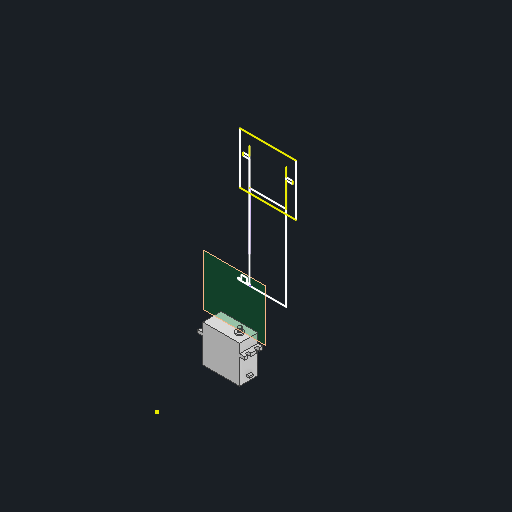
# Autodesk Inventor part: SERVO DS35MG IP67
Saved by Autodesk Inventor 2026.2 (Build 302298000, 298)
## iProperties
Created: 2026-01-28
Part Number: SERVO DS35MG IP67
Material: Generic
Document SubType Name: Modeling
Designer: thita
Density: 1 g/cm^3
Appearance: Default
Author: thita
Autodesk Inventor part; units mm, degrees
ref_plane "YZ Plane" through (0, 0, 0) normal (1, 0, 0) x (0, 1, 0)
ref_plane "XZ Plane" through (0, 0, 0) normal (0, 1, 0) x (-1, 0, 0)
ref_plane "XY Plane" through (0, 0, 0) normal (0, 0, 1) x (1, 0, 0)
sketch "Sketch1" plane through (0, 0, 0) normal (0, 1, 0) x (-1, 0, 0)
  line L0 (20, -10) -> (-20, -10)
  line L1 (-20, -10) -> (-20, 10)
  line L2 (-20, 10) -> (20, 10)
  line L3 (20, 10) -> (20, -10)
  line L4 (20, -10) -> (-20, 10) construction
  line L5 (-20, -10) -> (20, 10) construction
  point P0 (0, 0)
  dimension "d0" = 40
  dimension "d1" = 20
  constraints: 12 end point, 2 midpoint, 2 parallel, 1 horizontal, 1 perpendicular
  measures "d0" distance of L0.start L0.end
  measures "d1" distance of L0.end L1.end
extrude "Extrusion1" add sketch "Sketch1" along normal blind 40.5
sketch "Sketch2" plane through (0, 40.5, 0) normal (0, 1, 0) x (1, 0, 0)
  line L0 (20, -10) -> (20, 10) projected
  line L1 (20, 0) -> (10.2, 0)
  circle A0 centre (10.2, 0) radius 4
  point P0 (0, 0)
  dimension "d4" = 9.8
  dimension "d5" = 8
  constraints: 2 end point, 1 centre point, 1 coincident, 1 horizontal, 1 midpoint
  measures "d4" distance of L1.start L1.end
  measures "d5" diameter of A0
extrude "Extrusion2" add sketch "Sketch2" along normal blind 1.2
sketch "Sketch3" plane through (10.2, 41.7, 0) normal (0, 1, 0) x (1, 0, 0)
  circle A0 centre (0, 0) radius 2
  point P0 (-10.2, 0)
  dimension "d8" = 4
  constraints: 1 centre point
  measures "d8" diameter of A0
extrude "Extrusion3" add sketch "Sketch3" along normal blind 4.3
sketch "Sketch4" plane through (0, 0, 0) normal (0, -1, 0) x (1, 0, 0)
  arc A0 (25.5, -3.35) -> (25.5, -6.55) centre (24.3, -4.95) ccw
  arc A1 (-25.5, -6.55) -> (-25.5, -3.35) centre (-24.3, -4.95) ccw
  arc A2 (25.5, 6.55) -> (25.5, 3.35) centre (24.3, 4.95) ccw
  arc A3 (-25.5, 3.35) -> (-25.5, 6.55) centre (-24.3, 4.95) ccw
  line L0 (25.5, -6.55) -> (25.5, -10)
  line L1 (25.5, 10) -> (25.5, 6.55)
  line L2 (25.5, 3.35) -> (25.5, -3.35)
  line L3 (-25.5, 6.55) -> (-25.5, 10)
  line L4 (-25.5, -10) -> (-25.5, -6.55)
  line L5 (-25.5, -3.35) -> (-25.5, 3.35)
  line L6 (20, -10) -> (-20, -10) projected
  line L7 (25.5, -10) -> (20, -10)
  line L8 (20, -10) -> (20, 10)
  line L9 (20, 10) -> (25.5, 10)
  line L10 (-20, -10) -> (-25.5, -10)
  line L11 (-20, -10) -> (-20, 10) projected
  line L12 (-20, -10) -> (-20, 10)
  line L13 (-20, 10) -> (-25.5, 10)
  dimension "d14" = 4
  dimension "d15" = 4
  dimension "d16" = 4
  dimension "d17" = 4
  dimension "d19" = 20
  dimension "d20" = 20
  constraints: 24 end point, 10 parallel, 8 point on circle, 4 centre point, 3 perpendicular, 3 vertical, 1 collinear, 1 horizontal
  measures "d14" diameter of A0
  measures "d15" diameter of A1
  measures "d16" diameter of A2
  measures "d17" diameter of A3
  measures "d19" distance of L1.start L0.end
  measures "d20" distance of L4.start L3.end
extrude "Extrusion4" add sketch "Sketch4" against normal blind 30.5
sketch "Sketch5" plane through (0, 0, 0) normal (0, -1, 0) x (1, 0, 0)
  line L0 (20, -10) -> (-20, -10) projected
  line L1 (-20, 10) -> (20, 10) projected
  line L2 (20, -10) -> (20, 10)
  line L3 (-25.5, 10) -> (25.5, 10) projected
  line L4 (20, 10) -> (25.5, 10)
  line L5 (20, -10) -> (25.5, -10)
  arc A0 (25.5, -3.35) -> (25.5, -6.55) centre (24.3, -4.95) ccw projected
  arc A1 (25.5, -3.35) -> (25.5, -6.55) centre (24.3, -4.95) ccw
  arc A2 (25.5, 6.55) -> (25.5, 3.35) centre (24.3, 4.95) ccw projected
  arc A3 (25.5, 6.55) -> (25.5, 3.35) centre (24.3, 4.95) ccw
  line L6 (25.5, -10) -> (25.5, -6.55)
  line L7 (25.5, -3.35) -> (25.5, 3.35)
  line L8 (25.5, 6.55) -> (25.5, 10)
  line L9 (0, -10) -> (0, 10)
  line L10 (-20, -10) -> (-20, 10)
  line L11 (-20, 10) -> (-25.5, 10)
  line L12 (-20, -10) -> (-25.5, -10)
  arc A4 (-25.5, -6.55) -> (-25.5, -3.35) centre (-24.3, -4.95) ccw
  arc A5 (-25.5, -6.55) -> (-25.5, -3.35) centre (-24.3, -4.95) ccw
  arc A6 (-25.5, 3.35) -> (-25.5, 6.55) centre (-24.3, 4.95) ccw
  arc A7 (-25.5, 3.35) -> (-25.5, 6.55) centre (-24.3, 4.95) ccw
  line L13 (-25.5, -10) -> (-25.5, -6.55)
  line L14 (-25.5, -3.35) -> (-25.5, 3.35)
  line L15 (-25.5, 6.55) -> (-25.5, 10)
  point P0 (0, 0)
  point P1 (25.5, 3.35)
  constraints: 26 end point, 13 symmetric about line, 12 point on circle, 6 centre point, 4 coincident, 4 perpendicular, 2 midpoint, 1 collinear, 1 vertical, 4 other
extrude "Extrusion5" cut sketch "Sketch5" against normal blind 27.3 contours L2 L3 L8 A2 L7 A0 L6 L5 | L12 L13 A4 L14 A6 L15 L3 L10
sketch "Sketch6" plane through (10.2, 46, 0) normal (0, 1, 0) x (1, 0, 0)
  circle A0 centre (0, 0) radius 2 projected
  line L0 (0.0494, -1.9994) -> (0, -1.9)
  line L1 (-0.0494, -1.9994) -> (0, -1.9)
  line L2 (0.1748, -1.9923) -> (0.1193, -1.8963)
  line L3 (0.0763, -1.9985) -> (0.1193, -1.8963)
  line L4 (0.2996, -1.9774) -> (0.2381, -1.885)
  line L5 (0.2016, -1.9898) -> (0.2381, -1.885)
  line L6 (0.4232, -1.9547) -> (0.356, -1.8663)
  line L7 (0.3261, -1.9732) -> (0.356, -1.8663)
  line L8 (0.5451, -1.9243) -> (0.4725, -1.8403)
  line L9 (0.4494, -1.9489) -> (0.4725, -1.8403)
  line L10 (0.6648, -1.8863) -> (0.5871, -1.807)
  line L11 (0.5709, -1.9168) -> (0.5871, -1.807)
  line L12 (0.7819, -1.8408) -> (0.6994, -1.7666)
  line L13 (0.6901, -1.8772) -> (0.6994, -1.7666)
  line L14 (0.896, -1.7881) -> (0.809, -1.7192)
  line L15 (0.8066, -1.8301) -> (0.809, -1.7192)
  line L16 (1.0065, -1.7283) -> (0.9153, -1.665)
  line L17 (0.9199, -1.7759) -> (0.9153, -1.665)
  line L18 (1.113, -1.6617) -> (1.0181, -1.6042)
  line L19 (1.0296, -1.7146) -> (1.0181, -1.6042)
  line L20 (1.2152, -1.5885) -> (1.1168, -1.5371)
  line L21 (1.1353, -1.6466) -> (1.1168, -1.5371)
  line L22 (1.3125, -1.5091) -> (1.2111, -1.464)
  line L23 (1.2364, -1.572) -> (1.2111, -1.464)
  line L24 (1.4047, -1.4237) -> (1.3006, -1.385)
  line L25 (1.3327, -1.4913) -> (1.3006, -1.385)
  line L26 (1.4913, -1.3327) -> (1.385, -1.3006)
  line L27 (1.4237, -1.4047) -> (1.385, -1.3006)
  line L28 (1.572, -1.2364) -> (1.464, -1.2111)
  line L29 (1.5091, -1.3125) -> (1.464, -1.2111)
  line L30 (1.6466, -1.1353) -> (1.5371, -1.1168)
  line L31 (1.5885, -1.2152) -> (1.5371, -1.1168)
  line L32 (1.7146, -1.0296) -> (1.6042, -1.0181)
  line L33 (1.6617, -1.113) -> (1.6042, -1.0181)
  line L34 (1.7759, -0.9199) -> (1.665, -0.9153)
  line L35 (1.7283, -1.0065) -> (1.665, -0.9153)
  line L36 (1.8301, -0.8066) -> (1.7192, -0.809)
  line L37 (1.7881, -0.896) -> (1.7192, -0.809)
  line L38 (1.8772, -0.6901) -> (1.7666, -0.6994)
  line L39 (1.8408, -0.7819) -> (1.7666, -0.6994)
  line L40 (1.9168, -0.5709) -> (1.807, -0.5871)
  line L41 (1.8863, -0.6648) -> (1.807, -0.5871)
  line L42 (1.9489, -0.4494) -> (1.8403, -0.4725)
  line L43 (1.9243, -0.5451) -> (1.8403, -0.4725)
  line L44 (1.9732, -0.3261) -> (1.8663, -0.356)
  line L45 (1.9547, -0.4232) -> (1.8663, -0.356)
  line L46 (1.9898, -0.2016) -> (1.885, -0.2381)
  line L47 (1.9774, -0.2996) -> (1.885, -0.2381)
  line L48 (1.9985, -0.0763) -> (1.8963, -0.1193)
  line L49 (1.9923, -0.1748) -> (1.8963, -0.1193)
  line L50 (1.9994, 0.0494) -> (1.9, 0)
  line L51 (1.9994, -0.0494) -> (1.9, 0)
  line L52 (1.9923, 0.1748) -> (1.8963, 0.1193)
  line L53 (1.9985, 0.0763) -> (1.8963, 0.1193)
  line L54 (1.9774, 0.2996) -> (1.885, 0.2381)
  line L55 (1.9898, 0.2016) -> (1.885, 0.2381)
  line L56 (1.9547, 0.4232) -> (1.8663, 0.356)
  line L57 (1.9732, 0.3261) -> (1.8663, 0.356)
  line L58 (1.9243, 0.5451) -> (1.8403, 0.4725)
  line L59 (1.9489, 0.4494) -> (1.8403, 0.4725)
  line L60 (1.8863, 0.6648) -> (1.807, 0.5871)
  line L61 (1.9168, 0.5709) -> (1.807, 0.5871)
  line L62 (1.8408, 0.7819) -> (1.7666, 0.6994)
  line L63 (1.8772, 0.6901) -> (1.7666, 0.6994)
  line L64 (1.7881, 0.896) -> (1.7192, 0.809)
  line L65 (1.8301, 0.8066) -> (1.7192, 0.809)
  line L66 (1.7283, 1.0065) -> (1.665, 0.9153)
  line L67 (1.7759, 0.9199) -> (1.665, 0.9153)
  line L68 (1.6617, 1.113) -> (1.6042, 1.0181)
  line L69 (1.7146, 1.0296) -> (1.6042, 1.0181)
  line L70 (1.5885, 1.2152) -> (1.5371, 1.1168)
  line L71 (1.6466, 1.1353) -> (1.5371, 1.1168)
  line L72 (1.5091, 1.3125) -> (1.464, 1.2111)
  line L73 (1.572, 1.2364) -> (1.464, 1.2111)
  line L74 (1.4237, 1.4047) -> (1.385, 1.3006)
  line L75 (1.4913, 1.3327) -> (1.385, 1.3006)
  line L76 (1.3327, 1.4913) -> (1.3006, 1.385)
  line L77 (1.4047, 1.4237) -> (1.3006, 1.385)
  line L78 (1.2364, 1.572) -> (1.2111, 1.464)
  line L79 (1.3125, 1.5091) -> (1.2111, 1.464)
  line L80 (1.1353, 1.6466) -> (1.1168, 1.5371)
  line L81 (1.2152, 1.5885) -> (1.1168, 1.5371)
  line L82 (1.0296, 1.7146) -> (1.0181, 1.6042)
  line L83 (1.113, 1.6617) -> (1.0181, 1.6042)
  line L84 (0.9199, 1.7759) -> (0.9153, 1.665)
  line L85 (1.0065, 1.7283) -> (0.9153, 1.665)
  line L86 (0.8066, 1.8301) -> (0.809, 1.7192)
  line L87 (0.896, 1.7881) -> (0.809, 1.7192)
  line L88 (0.6901, 1.8772) -> (0.6994, 1.7666)
  line L89 (0.7819, 1.8408) -> (0.6994, 1.7666)
  line L90 (0.5709, 1.9168) -> (0.5871, 1.807)
  line L91 (0.6648, 1.8863) -> (0.5871, 1.807)
  line L92 (0.4494, 1.9489) -> (0.4725, 1.8403)
  line L93 (0.5451, 1.9243) -> (0.4725, 1.8403)
  line L94 (0.3261, 1.9732) -> (0.356, 1.8663)
  line L95 (0.4232, 1.9547) -> (0.356, 1.8663)
  line L96 (0.2016, 1.9898) -> (0.2381, 1.885)
  line L97 (0.2996, 1.9774) -> (0.2381, 1.885)
  line L98 (0.0763, 1.9985) -> (0.1193, 1.8963)
  line L99 (0.1748, 1.9923) -> (0.1193, 1.8963)
  line L100 (-0.0494, 1.9994) -> (0, 1.9)
  line L101 (0.0494, 1.9994) -> (0, 1.9)
  line L102 (-0.1748, 1.9923) -> (-0.1193, 1.8963)
  line L103 (-0.0763, 1.9985) -> (-0.1193, 1.8963)
  line L104 (-0.2996, 1.9774) -> (-0.2381, 1.885)
  line L105 (-0.2016, 1.9898) -> (-0.2381, 1.885)
  line L106 (-0.4232, 1.9547) -> (-0.356, 1.8663)
  line L107 (-0.3261, 1.9732) -> (-0.356, 1.8663)
  line L108 (-0.5451, 1.9243) -> (-0.4725, 1.8403)
  line L109 (-0.4494, 1.9489) -> (-0.4725, 1.8403)
  line L110 (-0.6648, 1.8863) -> (-0.5871, 1.807)
  line L111 (-0.5709, 1.9168) -> (-0.5871, 1.807)
  line L112 (-0.7819, 1.8408) -> (-0.6994, 1.7666)
  line L113 (-0.6901, 1.8772) -> (-0.6994, 1.7666)
  line L114 (-0.896, 1.7881) -> (-0.809, 1.7192)
  line L115 (-0.8066, 1.8301) -> (-0.809, 1.7192)
  line L116 (-1.0065, 1.7283) -> (-0.9153, 1.665)
  line L117 (-0.9199, 1.7759) -> (-0.9153, 1.665)
  line L118 (-1.113, 1.6617) -> (-1.0181, 1.6042)
  line L119 (-1.0296, 1.7146) -> (-1.0181, 1.6042)
  line L120 (-1.2152, 1.5885) -> (-1.1168, 1.5371)
  line L121 (-1.1353, 1.6466) -> (-1.1168, 1.5371)
  line L122 (-1.3125, 1.5091) -> (-1.2111, 1.464)
  line L123 (-1.2364, 1.572) -> (-1.2111, 1.464)
  line L124 (-1.4047, 1.4237) -> (-1.3006, 1.385)
  line L125 (-1.3327, 1.4913) -> (-1.3006, 1.385)
  line L126 (-1.4913, 1.3327) -> (-1.385, 1.3006)
  line L127 (-1.4237, 1.4047) -> (-1.385, 1.3006)
  line L128 (-1.572, 1.2364) -> (-1.464, 1.2111)
  line L129 (-1.5091, 1.3125) -> (-1.464, 1.2111)
  line L130 (-1.6466, 1.1353) -> (-1.5371, 1.1168)
  line L131 (-1.5885, 1.2152) -> (-1.5371, 1.1168)
  line L132 (-1.7146, 1.0296) -> (-1.6042, 1.0181)
  line L133 (-1.6617, 1.113) -> (-1.6042, 1.0181)
  line L134 (-1.7759, 0.9199) -> (-1.665, 0.9153)
  line L135 (-1.7283, 1.0065) -> (-1.665, 0.9153)
  line L136 (-1.8301, 0.8066) -> (-1.7192, 0.809)
  line L137 (-1.7881, 0.896) -> (-1.7192, 0.809)
  line L138 (-1.8772, 0.6901) -> (-1.7666, 0.6994)
  line L139 (-1.8408, 0.7819) -> (-1.7666, 0.6994)
  line L140 (-1.9168, 0.5709) -> (-1.807, 0.5871)
  line L141 (-1.8863, 0.6648) -> (-1.807, 0.5871)
  line L142 (-1.9489, 0.4494) -> (-1.8403, 0.4725)
  line L143 (-1.9243, 0.5451) -> (-1.8403, 0.4725)
  line L144 (-1.9732, 0.3261) -> (-1.8663, 0.356)
  line L145 (-1.9547, 0.4232) -> (-1.8663, 0.356)
  line L146 (-1.9898, 0.2016) -> (-1.885, 0.2381)
  line L147 (-1.9774, 0.2996) -> (-1.885, 0.2381)
  line L148 (-1.9985, 0.0763) -> (-1.8963, 0.1193)
  line L149 (-1.9923, 0.1748) -> (-1.8963, 0.1193)
  line L150 (-1.9994, -0.0494) -> (-1.9, 0)
  line L151 (-1.9994, 0.0494) -> (-1.9, 0)
  line L152 (-1.9923, -0.1748) -> (-1.8963, -0.1193)
  line L153 (-1.9985, -0.0763) -> (-1.8963, -0.1193)
  line L154 (-1.9774, -0.2996) -> (-1.885, -0.2381)
  line L155 (-1.9898, -0.2016) -> (-1.885, -0.2381)
  line L156 (-1.9547, -0.4232) -> (-1.8663, -0.356)
  line L157 (-1.9732, -0.3261) -> (-1.8663, -0.356)
  line L158 (-1.9243, -0.5451) -> (-1.8403, -0.4725)
  line L159 (-1.9489, -0.4494) -> (-1.8403, -0.4725)
  line L160 (-1.8863, -0.6648) -> (-1.807, -0.5871)
  line L161 (-1.9168, -0.5709) -> (-1.807, -0.5871)
  line L162 (-1.8408, -0.7819) -> (-1.7666, -0.6994)
  line L163 (-1.8772, -0.6901) -> (-1.7666, -0.6994)
  line L164 (-1.7881, -0.896) -> (-1.7192, -0.809)
  line L165 (-1.8301, -0.8066) -> (-1.7192, -0.809)
  line L166 (-1.7283, -1.0065) -> (-1.665, -0.9153)
  line L167 (-1.7759, -0.9199) -> (-1.665, -0.9153)
  line L168 (-1.6617, -1.113) -> (-1.6042, -1.0181)
  line L169 (-1.7146, -1.0296) -> (-1.6042, -1.0181)
  line L170 (-1.5885, -1.2152) -> (-1.5371, -1.1168)
  line L171 (-1.6466, -1.1353) -> (-1.5371, -1.1168)
  line L172 (-1.5091, -1.3125) -> (-1.464, -1.2111)
  line L173 (-1.572, -1.2364) -> (-1.464, -1.2111)
  line L174 (-1.4237, -1.4047) -> (-1.385, -1.3006)
  line L175 (-1.4913, -1.3327) -> (-1.385, -1.3006)
  line L176 (-1.3327, -1.4913) -> (-1.3006, -1.385)
  line L177 (-1.4047, -1.4237) -> (-1.3006, -1.385)
  line L178 (-1.2364, -1.572) -> (-1.2111, -1.464)
  line L179 (-1.3125, -1.5091) -> (-1.2111, -1.464)
  line L180 (-1.1353, -1.6466) -> (-1.1168, -1.5371)
  line L181 (-1.2152, -1.5885) -> (-1.1168, -1.5371)
  line L182 (-1.0296, -1.7146) -> (-1.0181, -1.6042)
  line L183 (-1.113, -1.6617) -> (-1.0181, -1.6042)
  line L184 (-0.9199, -1.7759) -> (-0.9153, -1.665)
  line L185 (-1.0065, -1.7283) -> (-0.9153, -1.665)
  line L186 (-0.8066, -1.8301) -> (-0.809, -1.7192)
  line L187 (-0.896, -1.7881) -> (-0.809, -1.7192)
  line L188 (-0.6901, -1.8772) -> (-0.6994, -1.7666)
  line L189 (-0.7819, -1.8408) -> (-0.6994, -1.7666)
  line L190 (-0.5709, -1.9168) -> (-0.5871, -1.807)
  line L191 (-0.6648, -1.8863) -> (-0.5871, -1.807)
  line L192 (-0.4494, -1.9489) -> (-0.4725, -1.8403)
  line L193 (-0.5451, -1.9243) -> (-0.4725, -1.8403)
  line L194 (-0.3261, -1.9732) -> (-0.356, -1.8663)
  line L195 (-0.4232, -1.9547) -> (-0.356, -1.8663)
  line L196 (-0.2016, -1.9898) -> (-0.2381, -1.885)
  line L197 (-0.2996, -1.9774) -> (-0.2381, -1.885)
  line L198 (-0.0763, -1.9985) -> (-0.1193, -1.8963)
  line L199 (-0.1748, -1.9923) -> (-0.1193, -1.8963)
  point P0 (-10.2, 0)
  point P1 (0.2996, 1.9774)
  point P2 (0.2016, 1.9898)
  dimension "d30" = 360
  constraints: 400 end point, 100 point on line, 2 point on circle, 601 other
extrude "Extrusion6" cut sketch "Sketch6" against normal up to surface (4.3 mm away) contours L97 L96 A0
pattern_circular "Circular Pattern1" count 100 over 360 about axis through (10.2, 41.7, 0) along (0, 1, 0) of "Extrusion6"
sketch "Sketch7" plane through (20, 0, 10) normal (1, 0, 0) x (0, 0, -1)
  line L0 (0, 0) -> (0, 7)
  line L1 (0, 27.3) -> (0, 0) projected
  line L2 (20, 0) -> (20, 27.3) projected
  line L3 (20, 7) -> (20, 0)
  line L4 (8, 5) -> (12, 5)
  line L5 (12, 5) -> (12, 7)
  line L6 (12, 7) -> (8, 7)
  line L7 (8, 7) -> (8, 5)
  line L8 (8, 5) -> (12, 7) construction
  line L9 (12, 5) -> (8, 7) construction
  point P0 (10, 0)
  point P1 (10, 6)
  dimension "d37" = 7
  dimension "d38" = 20
  dimension "d40" = 4
  dimension "d41" = 2
  constraints: 16 end point, 2 midpoint, 2 parallel, 1 perpendicular, 1 point on line
  measures "d37" distance of L0.start L0.end
  measures "d38" distance of L0.end L3.start
  measures "d40" distance of L4.start L4.end
  measures "d41" distance of L5.end L4.end
extrude "Extrusion7" add sketch "Sketch7" along normal blind 3
ref_plane "Work Plane1" through (114.6936, 124.552, 79.3975) normal (0, 0, -1) x (0, 1, 0)
sketch "Sketch8" plane through (114.6936, 124.552, 79.3975) normal (0, 0, -1) x (0, 1, 0)
  line L0 (188.168, 36.0285) -> (188.168, -24.9718) projected
  line L1 (132.168, 36.0287) -> (132.168, -24.9713) projected
  line L2 (188.168, 36.0285) -> (132.168, 36.0287)
  line L3 (188.168, -24.9718) -> (132.168, -24.9713)
  line L4 (164.168, 32.5287) -> (167.168, 32.5287) projected
  line L5 (167.168, 25.5287) -> (176.868, 25.5287) projected
  line L6 (51, -17.35) -> (46.5, -17.35)
  line L7 (51, -23.25) -> (46.5, -23.25)
  line L8 (176.868, -14.4713) -> (167.168, -14.4713) projected
  line L9 (167.168, -21.4713) -> (164.168, -21.4713) projected
  line L10 (137.468, 25.5287) -> (164.168, 25.5287) projected
  line L11 (137.168, 25.2287) -> (137.3215, 25.3823) projected
  line L12 (51, -17.35) -> (51, -23.25)
  line L13 (46.2, -26.75) -> (45, -26.75)
  line L14 (137.168, -14.1713) -> (137.3215, -14.3249) projected
  line L15 (46.5, -17.35) -> (46.5, -13.85)
  line L16 (46.5, -13.85) -> (45, -13.85)
  line L17 (45, -13.85) -> (45, 25.5287)
  line L18 (45, 25.5287) -> (167.168, 25.5287)
  line L19 (167.168, 25.5287) -> (167.168, 32.5287)
  line L20 (164.168, 32.5287) -> (164.168, 25.5287)
  line L21 (46.5, -23.25) -> (46.5, -26.75)
  line L22 (46.5, -26.75) -> (46.2, -26.75)
  line L23 (45, -26.75) -> (45, -14.4713)
  line L24 (45, -14.4713) -> (176.868, -14.4713)
  line L25 (167.168, -14.4713) -> (167.168, -21.4713)
  line L26 (164.168, -21.4713) -> (164.168, -14.4713)
  line L27 (164.168, -14.4713) -> (74.5691, -14.4713)
  line L28 (74.5691, -14.4713) -> (137.168, -14.1713)
  line L29 (137.168, -14.1713) -> (137.168, 25.2287)
  line L30 (137.468, 25.5287) -> (137.168, 25.2287)
  point P0 (-124.552, -114.6936)
  constraints: 44 end point, 5 perpendicular, 5 vertical, 3 horizontal, 2 collinear, 2 parallel, 2 point on line, 7 other
body "Solid1"
